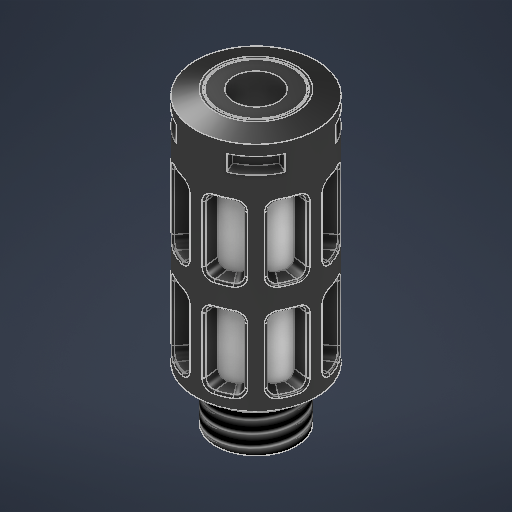
# Autodesk Inventor part: filter
Saved by Autodesk Inventor 2026.2 (Build 302298010, 298A)
## iProperties
Created: 2026-05-09
Part Number: filter
Material: ABS 플라스틱
Document SubType Name: Modeling
Designer: work
Density: 1.06 g/cm^3
Appearance: 피막 처리 - 검은색
Author: work
Autodesk Inventor part; units mm, degrees
sketch "스케치1" plane through (0, 0, 0) normal (0, 1, 0) x (-1, 0, 0)
  circle A0 centre (0, 0) radius 7.5
  dimension "d0" = 15
  constraints: 1 centre point, 1 coincident
  measures "d0" diameter of A0
extrude "돌출1" add sketch "스케치1" along normal blind 30
sketch "스케치2" plane through (0, 0, 0) normal (0, -1, 0) x (1, 0, 0)
  circle A0 centre (0, 0) radius 5
  dimension "d3" = 10
  constraints: 1 centre point, 1 coincident
  measures "d3" diameter of A0
extrude "돌출2" add sketch "스케치2" along normal blind 6
thread "스레드1" size "M10x1.5" class "6g" standard "ISO Metric profile" length 5 offset 1
sketch "스케치3" plane through (0, 0, 0) normal (0, -1, 0) x (1, 0, 0)
  circle A0 centre (0, 0) radius 5.5
  dimension "d8" = 11
  constraints: 1 centre point, 1 coincident
  measures "d8" diameter of A0
extrude "돌출3" add sketch "스케치3" along normal blind 1
sketch "스케치4" plane through (0, 30, 0) normal (0, 1, 0) x (1, 0, 0)
  circle A0 centre (0, 0) radius 2.75
  circle A1 centre (0, 0) radius 4.5
  circle A2 centre (0, 0) radius 4.7
  dimension "d11" = 5.5
  dimension "d12" = 9
  dimension "d13" = 0.2
  constraints: 3 centre point, 3 coincident
  measures "d11" diameter of A0
  measures "d12" diameter of A1
  measures "d13" radial gap between concentric circles of A2 A1
extrude "돌출4" cut sketch "스케치4" against normal blind 4 contours A0
extrude "돌출5" cut sketch "스케치4" against normal blind 0.2 contours A2
ref_plane "작업 평면1" through (0, 28, 0) normal (0, 1, 0) x (1, 0, 0)
sketch "스케치5" plane through (0, 28, 0) normal (0, 1, 0) x (1, 0, 0)
  circle A0 centre (0, 0) radius 7.5 projected
  circle A1 centre (0, 0) radius 6
  line L0 (0, 0) -> (6.7973, -3.1696)
  line L1 (0, 0) -> (3.1696, -6.7973)
  line L2 (0, 0) -> (0, -7.5) construction
  line L3 (0, 0) -> (3.1696, 6.7973)
  line L4 (0, 0) -> (6.7973, 3.1696)
  line L5 (0, 0) -> (-6.7973, 3.1696)
  line L6 (0, 0) -> (-3.1696, 6.7973)
  line L7 (0, 0) -> (-3.1696, -6.7973)
  line L8 (0, 0) -> (-6.7973, -3.1696)
  point P0 (-2.5357, 5.4378)
  point P1 (-5.4378, 2.5357)
  point P2 (-5.4378, -2.5357)
  point P3 (-2.5357, -5.4378)
  point P4 (2.5357, -5.4378)
  point P5 (5.4378, -2.5357)
  point P6 (5.4378, 2.5357)
  point P7 (2.5357, 5.4378)
  dimension "d19" = 1.5
  dimension "d20" = 40
  dimension "d21" = 25
  dimension "d24" = 360
  constraints: 18 end point, 3 coincident, 3 point on circle, 1 centre point, 1 vertical, 19 other
  measures "d19" radial gap between concentric circles of A0 A1
  measures "d20" angle of L1 L0
  measures "d21" angle of L1 L2
extrude "돌출6" cut sketch "스케치5" against normal blind 2 contours L4 A1 L3 A0 | A0 L1 A1 L0 | L6 A1 L5 A0 | A0 L8 A1 L7
chamfer "모따기1" distance 2.5 angle 15 1 edges at (7.5, 30, 0) measured on face at (7, 30, 0)
ref_plane "작업 평면2" through (0, 23, 0) normal (0, 1, 0) x (1, 0, 0)
sketch "스케치6" plane through (0, 23, 0) normal (0, 1, 0) x (1, 0, 0)
  circle A0 centre (0, 0) radius 7.5 projected
  line L0 (0, 0) -> (0, -7.5) construction
  line L1 (0, 0) -> (-1, -7.433)
  circle A1 centre (0, 0) radius 5.5
  line L2 (0, 0) -> (1, -7.433)
  line L3 (0, 0) -> (5.3033, -5.3033) construction
  line L4 (0, 0) -> (4.5488, -5.9631)
  line L5 (0, 0) -> (5.9631, -4.5488)
  line L6 (0, 0) -> (7.5, 0) construction
  line L7 (0, 0) -> (7.433, -1)
  line L8 (0, 0) -> (7.433, 1)
  line L9 (0, 0) -> (5.3033, 5.3033) construction
  line L10 (0, 0) -> (5.9631, 4.5488)
  line L11 (0, 0) -> (4.5488, 5.9631)
  line L12 (0, 0) -> (0, 7.5) construction
  line L13 (0, 0) -> (1, 7.433)
  line L14 (0, 0) -> (-1, 7.433)
  line L15 (0, 0) -> (-5.3033, 5.3033) construction
  line L16 (0, 0) -> (-4.5488, 5.9631)
  line L17 (0, 0) -> (-5.9631, 4.5488)
  line L18 (0, 0) -> (-7.5, 0) construction
  line L19 (0, 0) -> (-7.433, 1)
  line L20 (0, 0) -> (-7.433, -1)
  line L21 (0, 0) -> (-5.3033, -5.3033) construction
  line L22 (0, 0) -> (-5.9631, -4.5488)
  line L23 (0, 0) -> (-4.5488, -5.9631)
  point P0 (-3.3358, -4.3729)
  point P1 (-0.7333, -5.4509)
  point P2 (-4.3729, -3.3358)
  point P3 (-5.4509, -0.7333)
  point P4 (-5.4509, 0.7333)
  point P5 (-4.3729, 3.3358)
  point P6 (-3.3358, 4.3729)
  point P7 (-0.7333, 5.4509)
  point P8 (0.7333, 5.4509)
  point P9 (3.3358, 4.3729)
  point P10 (4.3729, 3.3358)
  point P11 (5.4509, 0.7333)
  point P12 (5.4509, -0.7333)
  point P13 (4.3729, -3.3358)
  point P14 (3.3358, -4.3729)
  point P15 (0.7333, -5.4509)
  dimension "d32" = 2
  dimension "d33" = 2
  dimension "d36" = 360
  constraints: 48 end point, 2 point on circle, 1 centre point, 1 coincident, 1 symmetric about line, 1 vertical, 65 other
  measures "d32" radial gap between concentric circles of A0 A1
  measures "d33" distance of L1.end L2.end
extrude "돌출7" cut sketch "스케치6" against normal blind 9 contours L8 A1 L10 A0 | A0 L5 A1 L7 | L11 A1 L13 A0 | A0 L2 A1 L4 | L1 A0 L23 A1 | A1 L16 A0 L14 | A1 L19 A0 L17 | A1 L22 A0 L20
ref_plane "작업 평면3" through (0, 12.5, 0) normal (0, 1, 0) x (1, 0, 0)
fillet "모깎기1" radius 1 4 edges at (0.8667, 23, -6.442) (3.9423, 23, -5.168) (3.9423, 14, -5.168) (0.8667, 14, -6.442)
fillet "모깎기2" radius 0.25 8 edges at (4.5488, 18.5, -5.9631) (4.3399, 14.3281, -6.1168) (2.8701, 14, -6.9291) (1.2566, 14.3279, -7.394) (1, 18.5, -7.433) (1.2566, 22.6721, -7.394) (2.8701, 23, -6.9291) (4.3398, 22.672, -6.1169)
pattern_circular "원형 패턴1" count 8 over 360 about axis through (0, -10, 0) along (0, 1, 0) of "돌출7", "모깎기1", "모깎기2"
mirror "미러1" about plane through (0, 12.5, 0) normal (0, 1, 0) of "돌출7"
fillet "모깎기3" radius 1 4 edges at (-0.8667, 11, -6.442) (-3.9423, 11, -5.168) (-3.9423, 2, -5.168) (-0.8667, 2, -6.442)
fillet "모깎기4" radius 0.25 8 edges at (-1.2566, 10.672, -7.394) (-2.8701, 11, -6.9291) (-4.3399, 10.6719, -6.1168) (-4.5488, 6.5, -5.9631) (-4.3399, 2.3281, -6.1168) (-2.8701, 2, -6.9291) (-1.2564, 2.3281, -7.394) (-1, 6.5, -7.433)
pattern_circular "원형 패턴2" count 8 over 360 about axis through (0, -10, 0) along (0, 1, 0) of "모깎기3", "모깎기4"
chamfer "모따기2" distance 2 angle 15 1 edges at (7.5, 0, 0) measured on face at (7, 0, 0)
